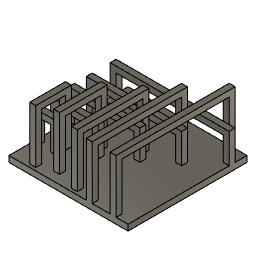
Bridging test v2 v1 (Autodesk Fusion 360 design; units mm, degrees)
Autodesk Fusion 360 part; units mm, degrees
sketch "Sketch1" plane through (0, 0, 0) normal (0, 0, 1) x (1, 0, 0)
  line L0 (0, 0) -> (200, 0)
  line L1 (200, 0) -> (200, 200)
  line L2 (200, 200) -> (0, 200)
  line L3 (0, 200) -> (0, 0)
  dimension "d1" = 200
  dimension "d2" = 200
  constraint horizontal L0
  constraint vertical L1
  constraint horizontal L2
  constraint vertical L3
  constraint coincident L0.start L3.end
  measures "d1" distance of L0.start L0.end
  measures "d2" distance of L0.start L2.end
extrude "Extrude1" add sketch "Sketch1" along normal blind 10
ref_plane "WorkPlane1" through (100, 40, 5) normal (0, -1, 0) x (1, 0, 0)
ref_plane "WorkPlane2" through (100, 70, 5) normal (0, -1, 0) x (1, 0, 0)
sketch "Sketch2" plane through (100, 40, 5) normal (0, -1, 0) x (1, 0, 0)
  line L0 (-100, 5) -> (-100, 55)
  line L1 (-100, 55) -> (-60, 55)
  line L2 (-60, 55) -> (-60, 5)
  line L3 (-100, 5) -> (-90, 5)
  line L4 (-90, 5) -> (-90, 45)
  line L5 (-90, 45) -> (-70, 45)
  line L6 (-70, 45) -> (-70, 5)
  line L7 (-70, 5) -> (-60, 5)
  dimension "d7" = 50
  dimension "d8" = 40
  dimension "d9" = 50
  dimension "d10" = 10
  dimension "d11" = 40
  dimension "d12" = 20
  dimension "d13" = 40
  constraint vertical L0
  constraint perpendicular L0 L1
  constraint perpendicular L1 L2
  constraint perpendicular L0 L3
  constraint perpendicular L3 L4
  constraint perpendicular L4 L5
  constraint perpendicular L5 L6
  measures "d7" distance of L0.start L0.end
  measures "d8" distance of L0.end L1.end
  measures "d9" distance of L1.end L2.end
  measures "d10" distance of L0.start L3.end
  measures "d11" distance of L3.end L4.end
  measures "d12" distance of L4.end L5.end
  measures "d13" distance of L5.end L6.end
extrude "Extrude2" add sketch "Sketch2" against normal blind 10
ref_plane "WorkPlane3" through (40, 0, 0) normal (1, 0, 0) x (0, 1, 0)
sketch "Sketch3" plane through (40, 0, 0) normal (1, 0, 0) x (0, 1, 0)
  line L0 (0, 10) -> (5, 10)
  line L1 (5, 10) -> (5, 100)
  line L2 (5, 100) -> (65, 100)
  line L3 (65, 100) -> (65, 10)
  line L4 (65, 10) -> (55, 10)
  line L5 (55, 10) -> (55, 90)
  line L6 (55, 90) -> (15, 90)
  line L7 (15, 90) -> (15, 10)
  line L8 (15, 10) -> (5, 10)
  dimension "d17" = 5
  dimension "d18" = 90
  dimension "d19" = 60
  dimension "d20" = 90
  dimension "d21" = 10
  dimension "d22" = 80
  dimension "d23" = 40
  constraint horizontal L0
  constraint perpendicular L0 L1
  constraint perpendicular L1 L2
  constraint perpendicular L0 L3
  constraint perpendicular L3 L4
  constraint perpendicular L4 L5
  constraint perpendicular L3 L6
  constraint perpendicular L6 L7
  constraint perpendicular L1 L8
  measures "d17" distance of L0.start L0.end
  measures "d18" distance of L0.end L1.end
  measures "d19" distance of L1.end L2.end
  measures "d20" distance of L2.end L3.end
  measures "d21" distance of L3.end L4.end
  measures "d22" distance of L4.end L5.end
  measures "d23" distance of L5.end L6.end
extrude "Extrude3" add sketch "Sketch3" against normal blind 10
sketch "Sketch4" plane through (100, 70, 5) normal (0, -1, 0) x (1, 0, 0)
  line L0 (-100, 5) -> (-100, 55)
  line L1 (-100, 55) -> (-20, 55)
  line L2 (-20, 55) -> (-20, 5)
  line L3 (-20, 5) -> (-30, 5)
  line L4 (-30, 5) -> (-30, 45)
  line L5 (-30, 45) -> (-90, 45)
  line L6 (-90, 45) -> (-90, 5)
  line L7 (-90, 5) -> (-100, 5)
  dimension "d26" = 80
  dimension "d27" = 50
  dimension "d28" = 10
  dimension "d29" = 40
  dimension "d30" = 60
  constraint vertical L0
  constraint perpendicular L0 L1
  constraint perpendicular L1 L2
  constraint perpendicular L2 L3
  constraint perpendicular L1 L4
  constraint perpendicular L4 L5
  constraint perpendicular L5 L6
  constraint perpendicular L0 L7
  measures "d26" distance of L0.end L1.end
  measures "d27" distance of L1.end L2.end
  measures "d28" distance of L2.end L3.end
  measures "d29" distance of L3.end L4.end
  measures "d30" distance of L4.end L5.end
extrude "Extrude4" add sketch "Sketch4" against normal blind 10
ref_plane "WorkPlane4" through (70, 100, 30) normal (-1, 0, 0) x (0, -1, 0)
sketch "Sketch5" plane through (70, 100, 30) normal (-1, 0, 0) x (0, 1, 0)
  line L0 (-100, 20) -> (-85, 20)
  line L1 (-85, 20) -> (-85, -70)
  line L2 (-85, -70) -> (-5, -70)
  line L3 (-5, -70) -> (-5, 20)
  line L4 (-5, 20) -> (-15, 20)
  line L5 (-15, 20) -> (-15, -60)
  line L6 (-15, -60) -> (-75, -60)
  line L7 (-75, -60) -> (-75, 20)
  line L8 (-75, 20) -> (-85, 20)
  dimension "d34" = 15
  dimension "d35" = 90
  dimension "d36" = 80
  dimension "d37" = 90
  dimension "d38" = 80
  dimension "d39" = 60
  dimension "d40" = 80
  constraint horizontal L0
  constraint perpendicular L0 L1
  constraint perpendicular L1 L2
  constraint perpendicular L2 L3
  constraint perpendicular L3 L4
  constraint perpendicular L4 L5
  constraint perpendicular L5 L6
  constraint perpendicular L6 L7
  measures "d34" distance of L0.start L0.end
  measures "d35" distance of L0.end L1.end
  measures "d36" distance of L1.end L2.end
  measures "d37" distance of L2.end L3.end
  measures "d38" distance of L4.end L5.end
  measures "d39" distance of L5.end L6.end
  measures "d40" distance of L6.end L7.end
extrude "Extrude5" add sketch "Sketch5" along normal blind 10
ref_plane "WorkPlane5" through (100, 100, 5) normal (0, -1, 0) x (1, 0, 0)
sketch "Sketch6" plane through (100, 100, 5) normal (0, -1, 0) x (1, 0, 0)
  line L0 (-100, 5) -> (-100, 55)
  line L1 (-100, 55) -> (20, 55)
  line L2 (20, 55) -> (20, 5)
  line L3 (20, 5) -> (10, 5)
  line L4 (10, 5) -> (10, 45)
  line L5 (10, 45) -> (-90, 45)
  line L6 (-90, 45) -> (-90, 5)
  line L7 (-90, 5) -> (-100, 5)
  dimension "d44" = 120
  dimension "d45" = 50
  dimension "d46" = 10
  dimension "d47" = 40
  dimension "d48" = 100
  constraint vertical L0
  constraint perpendicular L0 L1
  constraint perpendicular L1 L2
  constraint perpendicular L0 L3
  constraint perpendicular L3 L4
  constraint perpendicular L4 L5
  constraint perpendicular L3 L6
  constraint perpendicular L0 L7
  measures "d44" distance of L0.end L1.end
  measures "d45" distance of L1.end L2.end
  measures "d46" distance of L2.end L3.end
  measures "d47" distance of L3.end L4.end
  measures "d48" distance of L4.end L5.end
extrude "Extrude6" add sketch "Sketch6" against normal blind 10
ref_plane "WorkPlane6" through (100, 100, 30) normal (-1, 0, 0) x (0, -1, 0)
sketch "Sketch7" plane through (100, 100, 30) normal (-1, 0, 0) x (0, 1, 0)
  line L0 (-100, 20) -> (-95, 20)
  line L1 (-95, 20) -> (-95, -70)
  line L2 (-95, -70) -> (25, -70)
  line L3 (25, -70) -> (25, 20)
  line L4 (25, 20) -> (15, 20)
  line L5 (15, 20) -> (15, -60)
  line L6 (15, -60) -> (-85, -60)
  line L7 (-85, -60) -> (-85, 20)
  line L8 (-85, 20) -> (-95, 20)
  dimension "d52" = 90
  dimension "d53" = 120
  dimension "d54" = 90
  dimension "d55" = 10
  dimension "d56" = 80
  constraint horizontal L0
  constraint perpendicular L0 L1
  constraint perpendicular L1 L2
  constraint perpendicular L2 L3
  constraint perpendicular L1 L4
  constraint perpendicular L2 L5
  constraint perpendicular L1 L6
  constraint perpendicular L6 L7
  constraint perpendicular L1 L8
  measures "d52" distance of L0.end L1.end
  measures "d53" distance of L1.end L2.end
  measures "d54" distance of L2.end L3.end
  measures "d55" distance of L3.end L4.end
  measures "d56" distance of L4.end L5.end
extrude "Extrude7" add sketch "Sketch7" against normal blind 10
ref_plane "WorkPlane7" through (100, 130, 5) normal (0, -1, 0) x (1, 0, 0)
sketch "Sketch8" plane through (100, 130, 5) normal (0, -1, 0) x (1, 0, 0)
  line L0 (-100, 5) -> (-100, 55)
  line L1 (-100, 55) -> (60, 55)
  line L2 (60, 55) -> (60, 5)
  line L3 (60, 5) -> (50, 5)
  line L4 (50, 5) -> (50, 45)
  line L5 (50, 45) -> (-90, 45)
  line L6 (-90, 45) -> (-90, 5)
  line L7 (-90, 5) -> (-100, 5)
  dimension "d60" = 50
  dimension "d61" = 160
  dimension "d62" = 50
  dimension "d63" = 10
  dimension "d64" = 40
  dimension "d65" = 140
  dimension "d66" = 10
  constraint vertical L0
  constraint perpendicular L0 L1
  constraint perpendicular L1 L2
  constraint perpendicular L2 L3
  constraint perpendicular L1 L4
  constraint perpendicular L4 L5
  constraint perpendicular L1 L6
  constraint perpendicular L0 L7
  measures "d60" distance of L0.start L0.end
  measures "d61" distance of L0.end L1.end
  measures "d62" distance of L1.end L2.end
  measures "d63" distance of L2.end L3.end
  measures "d64" distance of L3.end L4.end
  measures "d65" distance of L4.end L5.end
  measures "d66" distance of L6.end L0.start
extrude "Extrude8" add sketch "Sketch8" against normal blind 10
ref_plane "WorkPlane8" through (130, 100, 30) normal (-1, 0, 0) x (0, -1, 0)
sketch "Sketch9" plane through (130, 100, 30) normal (-1, 0, 0) x (0, 1, 0)
  line L0 (-100, 20) -> (-95, 20)
  line L1 (-100, 20) -> (-100, -70)
  line L2 (-100, -70) -> (60, -70)
  line L3 (60, -70) -> (60, 20)
  line L4 (60, 20) -> (50, 20)
  line L5 (50, 20) -> (50, -60)
  line L6 (50, -60) -> (-90, -60)
  line L7 (-90, -60) -> (-90, 20)
  line L8 (-90, 20) -> (-100, 20)
  dimension "d70" = 5
  dimension "d73" = 90
  dimension "d74" = 160
  dimension "d75" = 90
  dimension "d76" = 80
  dimension "d77" = 140
  constraint horizontal L0
  constraint perpendicular L0 L1
  constraint perpendicular L1 L2
  constraint perpendicular L2 L3
  constraint perpendicular L3 L4
  constraint perpendicular L2 L5
  constraint perpendicular L3 L6
  constraint perpendicular L6 L7
  constraint perpendicular L1 L8
  measures "d70" distance of L0.start L0.end
  measures "d73" distance of L0.start L1.end
  measures "d74" distance of L1.end L2.end
  measures "d75" distance of L2.end L3.end
  measures "d76" distance of L4.end L5.end
  measures "d77" distance of L5.end L6.end
extrude "Extrude9" add sketch "Sketch9" against normal blind 10
ref_plane "WorkPlane9" through (100, 170, 50) normal (0, -1, 0) x (1, 0, 0)
sketch "Sketch10" plane through (100, 170, 50) normal (0, -1, 0) x (1, 0, 0)
  line L0 (-100, -40) -> (-100, 10)
  line L1 (-100, 10) -> (100, 10)
  line L2 (100, 10) -> (100, -40)
  line L3 (100, -40) -> (90, -40)
  line L4 (90, -40) -> (90, 0)
  line L5 (90, 0) -> (-90, 0)
  line L6 (-90, 0) -> (-90, -40)
  line L7 (-90, -40) -> (-100, -40)
  dimension "d81" = 50
  dimension "d82" = 200
  dimension "d83" = 10
  dimension "d84" = 40
  dimension "d85" = 180
  dimension "d86" = 10
  constraint vertical L0
  constraint perpendicular L0 L1
  constraint perpendicular L1 L2
  constraint perpendicular L2 L3
  constraint perpendicular L3 L4
  constraint perpendicular L2 L5
  constraint perpendicular L5 L6
  constraint perpendicular L0 L7
  measures "d81" distance of L0.start L0.end
  measures "d82" distance of L0.end L1.end
  measures "d83" distance of L2.end L3.end
  measures "d84" distance of L3.end L4.end
  measures "d85" distance of L4.end L5.end
  measures "d86" distance of L6.end L0.start
extrude "Extrude10" add sketch "Sketch10" against normal blind 10
ref_plane "WorkPlane10" through (170, 100, 30) normal (-1, 0, 0) x (0, -1, 0)
sketch "Sketch11" plane through (170, 100, 30) normal (-1, 0, 0) x (0, 1, 0)
  line L0 (-100, 20) -> (-100, -70)
  line L1 (-100, -70) -> (100, -70)
  line L2 (100, -70) -> (100, 20)
  line L3 (100, 20) -> (90, 20)
  line L4 (90, 20) -> (90, -60)
  line L5 (90, -60) -> (-90, -60)
  line L6 (-90, -60) -> (-90, 20)
  line L7 (-90, 20) -> (-100, 20)
  dimension "d90" = 200
  dimension "d91" = 80
  dimension "d92" = 180
  constraint vertical L0
  constraint perpendicular L0 L1
  constraint perpendicular L1 L2
  constraint perpendicular L2 L3
  constraint perpendicular L1 L4
  constraint perpendicular L4 L5
  constraint perpendicular L5 L6
  constraint perpendicular L0 L7
  measures "d90" distance of L0.end L1.end
  measures "d91" distance of L3.end L4.end
  measures "d92" distance of L4.end L5.end
extrude "Extrude11" add sketch "Sketch11" against normal blind 10
